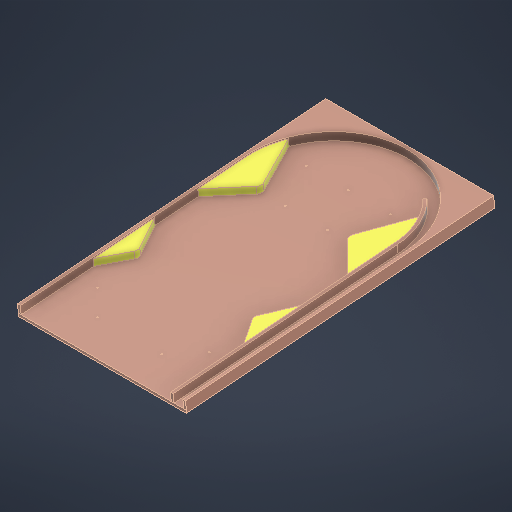
# Autodesk Inventor part: Playfield
Saved by Autodesk Inventor 2027 (Build 310192060, 192F)
## iProperties
Created: 2026-10-17
Part Number: Playfield
Material: Générique
Document SubType Name: Modeling
Designer: strei
Density: 1 g/cm^3
Appearance: Lisse - Brun foncé
Author: strei
Autodesk Inventor part; units mm, degrees
ref_plane "XZ Plane" through (0, 0, 0) normal (0, 1, 0) x (-1, 0, 0)
ref_plane "XY Plane" through (0, 0, 0) normal (0, 0, 1) x (1, 0, 0)
ref_plane "Plan de construction1" through (-22, 0, 0) normal (1, 0, 0) x (0, 1, 0)
sketch "Esquisse1" plane through (0, 0, 0) normal (1, 0, 0) x (0, 1, 0)
  line L0 (-32.2906, 549.9992) -> (52.3497, -549.9992)
  line L1 (52.3497, -549.9992) -> (42.3201, -549.9992)
  line L2 (42.3201, -549.9992) -> (-42.3201, 549.9992)
  line L3 (-42.3201, 549.9992) -> (-32.2906, 549.9992)
  point P0 (0, 0)
  point P1 (0, 0)
  dimension "d0" = 94.4
  dimension "d1" = 10
  dimension "d2" = 1103.25
  constraints: 8 end point, 2 horizontal, 1 coincident, 1 midpoint, 1 parallel
  measures "d0" angle of L0 L3
  measures "d1" distance between parallel lines of L2 L0
  measures "d2" distance of L0.start L0.end
extrude "Extrusion1" add sketch "Esquisse1" along normal mid plane 600
sketch "Esquisse2" plane through (-300, -32.2906, 549.9992) normal (0, 0.9970528, 0.076719) x (1, 0, 0)
  line L0 (163, 120) -> (393, 120) construction
  line L1 (0, 0) -> (600, 0) projected
  line L2 (278, 1324.0539) -> (278, -221.5733) projected
  point P0 (300, 550.8555)
  point P1 (300, 0)
  point P2 (278, 120)
  point P3 (300, 0)
  dimension "d5" = 230
  dimension "d6" = 120
  constraints: 3 midpoint, 2 end point, 1 horizontal, 1 point on line
  measures "d5" distance of L0.end L0.start
  measures "d6" distance between parallel lines of L1 L0
hole "Perçage1" at (-137, -23.0843, 430.3529) at (93, -23.0843, 430.3529) direction (0, -0.9970528, -0.076719) diameter 5 end through all
sketch "Esquisse3" plane through (-300, -32.2906, 549.9992) normal (0, 0.9970528, 0.076719) x (1, 0, 0)
  circle A0 centre (163, 120) radius 2.5 projected
  circle A1 centre (163, 120) radius 15 construction
  circle A2 centre (163, 120) radius 20
  line L0 (177.1421, 134.1421) -> (92.2893, 218.9949)
  circle A3 centre (78.1472, 204.8528) radius 20
  line L1 (64.0051, 190.7107) -> (148.8579, 105.8579)
  line L2 (78.1472, 204.8528) -> (163, 120) construction
  line L3 (0, 0) -> (600, 0) projected
  point P0 (300, 550.8555)
  point P1 (78.1472, 204.8528)
  dimension "d14" = 30
  dimension "d15" = 40
  dimension "d16" = 40
  dimension "d17" = 120
  dimension "d18" = 45
  constraints: 6 end point, 4 point on circle, 4 tangent, 3 centre point, 3 coincident
  measures "d14" diameter of A1
  measures "d15" diameter of A2
  measures "d16" diameter of A3
  measures "d17" distance of L2.start L2.end
  measures "d18" angle of L3 L2
hole "Perçage3" at (-221.8528, -16.5745, 345.7502) direction (0, -0.9970528, -0.076719) diameter 5 end through all
mirror "Mise en miroir4" about plane through (-22, 0, 0) normal (1, 0, 0) of "Perçage3"
sketch "Esquisse4" plane through (-300, -32.2906, 549.9992) normal (0, 0.9970528, 0.076719) x (1, 0, 0)
  line L0 (128, 903.25) -> (428, 903.25) construction
  line L1 (203, 753.25) -> (353, 753.25) construction
  line L2 (0, 1103.25) -> (600, 1103.25) projected
  line L3 (278, 1324.0539) -> (278, -221.5733) projected
  point P0 (300, 550.8555)
  point P1 (278, 903.25)
  point P2 (300, 1103.25)
  point P3 (278, 753.25)
  point P4 (300, 1103.25)
  point P5 (278, 903.25)
  dimension "d22" = 300
  dimension "d23" = 150
  dimension "d24" = 150
  dimension "d25" = 200
  constraints: 5 coincident, 4 end point, 4 midpoint, 2 horizontal, 2 point on line
  measures "d22" distance of L0.start L0.end
  measures "d23" distance of L1.start L1.end
  measures "d24" distance between parallel lines of L1 L0
  measures "d25" distance between parallel lines of L0 L2
hole "Perçage2" at (-172, 37.0059, -350.5887) at (128, 37.0059, -350.5887) at (-22, 37.0059, -350.5887) at (-97, 25.498, -201.0308) at (53, 25.498, -201.0308) direction (0, -0.9970528, -0.076719) diameter 5 depth 10
sketch "Esquisse5" plane through (-300, -32.2906, 549.9992) normal (0, 0.9970528, 0.076719) x (1, 0, 0)
  circle A0 centre (300, 802.4805) radius 290
  line L0 (0, 1103.25) -> (600, 1103.25) projected
  line L1 (0, 0) -> (0, 1103.25) projected
  line L2 (600, 1103.25) -> (600, 0) projected
  line L3 (0, 1102.4805) -> (600, 1102.4805) projected
  line L4 (0, 1102.4805) -> (590, 1102.4805)
  line L5 (590, 1102.4805) -> (590, 802.4805)
  line L6 (590, 802.4805) -> (0, 802.4805)
  line L7 (0, 802.4805) -> (0, 1102.4805)
  line L8 (600, 0) -> (590, 0)
  line L9 (590, 0) -> (590, 1102.4805)
  line L10 (590, 1102.4805) -> (600, 1102.4805)
  line L11 (600, 1102.4805) -> (600, 0)
  line L12 (0, 0) -> (600, 0) projected
  line L13 (546, 802.4805) -> (556, 802.4805)
  line L14 (556, 802.4805) -> (556, 0)
  line L15 (556, 0) -> (546, 0)
  line L16 (546, 0) -> (546, 802.4805)
  circle A1 centre (300, 802.4805) radius 256
  circle A2 centre (300, 802.4805) radius 246
  line L17 (300, 802.4805) -> (481.0193, 983.4999)
  line L18 (0, 1102.4805) -> (10, 1102.4805)
  line L19 (10, 1102.4805) -> (10, 0)
  line L20 (10, 0) -> (0, 0)
  line L21 (0, 0) -> (0, 1102.4805)
  point P0 (300, 550.8555)
  point P1 (300, 1102.4805)
  point P2 (0, 782.4805)
  point P3 (600, 782.4805)
  point P4 (473.9483, 976.4288)
  point P5 (546, 0)
  point P6 (10, 802.4805)
  point P7 (590, 1102.4805)
  dimension "d33" = 300
  dimension "d36" = 10
  dimension "d37" = 10
  dimension "d38" = 34
  dimension "d39" = 45
  dimension "d40" = 10
  constraints: 34 end point, 8 parallel, 5 point on line, 4 horizontal, 4 perpendicular, 2 coincident, 2 point on circle, 1 centre point, 1 collinear, 1 midpoint, 1 vertical, 6 other
  measures "d33" distance from line of point (300, 1102.481) L6
  measures "d36" distance between parallel lines of L2 L9
  measures "d37" distance between parallel lines of L14 L16
  measures "d38" distance between parallel lines of L9 L14
  measures "d39" angle of L6 L17
  measures "d40" distance between parallel lines of L19 L21
extrude "Extrusion3" add sketch "Esquisse5" along normal blind 30 contours A0 L19 L3 L5 | L5 L3 L2 L8 L9 | L19 L12 L1 L6 | L6 L1 L3 L19 | L14 L12 L16 A0 | A0 L16 A1 L14 | L3 L1 L0 L2 | A1 L16 L6 | L6 A2 L17 A1 picked at (488.5245, 970.3801)
sketch "Esquisse6" plane through (0, 29.275, -250.1162) normal (0, 0.9970528, 0.076719) x (1, 0, 0)
  arc A0 (290, 0) -> (-290, 0) centre (0, 0) ccw projected
  line L0 (-260.4042, 127.6308) -> (-181.8738, -40.7782)
  circle A1 centre (-200, -49.2305) radius 20
  line L1 (-290, -802.4805) -> (-290, 0) projected
  line L2 (-290, -167.5148) -> (-185.8579, -63.3727)
  line L3 (-300, 300.7695) -> (-300, -802.4805) projected
  line L4 (-200, -49.2305) -> (-300, -49.2305) construction
  line L5 (300, 300.7695) -> (-300, 300.7695) projected
  point P0 (0, -251.625)
  dimension "d41" = 40
  dimension "d42" = 100
  dimension "d43" = 65
  dimension "d44" = 45
  dimension "d45" = 350
  constraints: 6 end point, 3 point on circle, 2 point on line, 2 tangent, 1 centre point, 1 perpendicular
  measures "d41" diameter of A1
  measures "d42" distance from line of L4.start L3
  measures "d43" angle of L0 L4
  measures "d44" angle of L2 L4
  measures "d45" distance between parallel lines of L5 L4
extrude "Extrusion4" add sketch "Esquisse6" along normal blind 25
mirror "Mise en miroir2" about plane through (-22, 0, 0) normal (1, 0, 0) of "Extrusion4"
sketch "Esquisse7" plane through (-290, -32.2906, 549.9992) normal (0, 0.9970528, 0.076719) x (1, 0, 0)
  circle A0 centre (40, 360) radius 20
  line L0 (0, 634.9657) -> (0, 0) projected
  line L1 (0, 480) -> (57.735, 369.245)
  line L2 (0, 260) -> (56.8673, 349.2531)
  line L3 (-10, 1103.25) -> (-10, 0) projected
  line L4 (0, 0) -> (536, 0) projected
  point P0 (290, 550.8555)
  dimension "d50" = 40
  dimension "d51" = 50
  dimension "d52" = 120
  dimension "d53" = 100
  dimension "d54" = 360
  constraints: 4 end point, 2 point on circle, 2 point on line, 2 tangent, 1 centre point
  measures "d50" diameter of A0
  measures "d51" distance from line of L3 A0.centre
  measures "d52" vertical distance of L1.start A0.centre
  measures "d53" vertical distance of L2.start A0.centre
  measures "d54" distance from line of L4 A0.centre
extrude "Extrusion5" add sketch "Esquisse7" along normal blind 25
mirror "Mise en miroir3" about plane through (-22, 0, 0) normal (1, 0, 0) of "Extrusion5"
equation "\"d40\" = d36"
